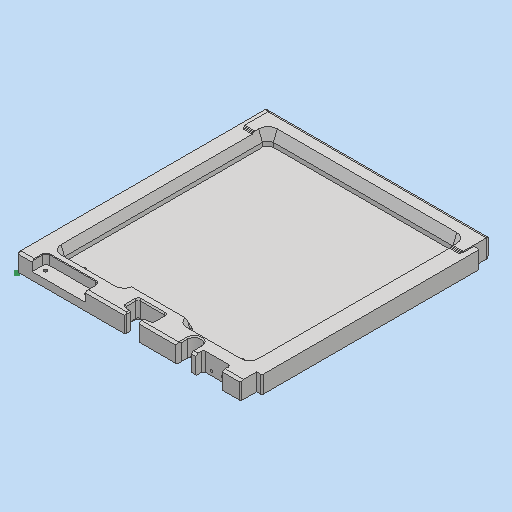
# Autodesk Inventor part: MN0555AN106_G01_100
Saved by Autodesk Inventor 2023.3 (Build 273359000, 359)
## iProperties
RuleStatus: InUse
Created: 2022-12-23
Part Number: MN0555AN106_G01_100
Material: 1.2210 115CrV3
Description: =<RBPARTNOTITLE2>
Document SubType Name: Modeling
Designer: ric7an
Mass: 3076.42 g
Surface Area: 1198.55 cm^2
Volume: 394.412 cm^3
Density: 7.8 g/cm^3
Appearance: silber AnP
AnP_Kategorie: 1
AnP_Material: =<Material>
MaxAbmaße: 18 x 275 x 212 (FM)
AnP_TemplVers: 20200821
RBDOCUMENTTYPE: DRF
RBDOCUMENTVERSION: 00
RBDRAWINGMAINSCALE: 1:1
RBDRAWINGMISSINGSPEC: --
RBDRAWINGVOLUME: --
RBDSV1: 0850
RBGBEDGESIN1: +0,5
RBGBEDGESIN2: +0,2
RBGBEDGESOUT1: -0,3
RBGBEDGESOUT2: -0,1
RBMATERIAL: =<Material>
RBMATMEETS: --
RBMATNO: =<Part Number>
RBPARTMADEOF: 18 x 275 x 212 (FM)
RBPARTNO: SIEHE MNR
RBPARTNOTITLE1: manufactured part
RBPARTNOTITLE2: Anfertigungsteil
RBPARTSAFETYINDICATOR: --
RBSURFACE: chemically nickel-coated
RBSURFACE2: chem. vernickelt
RBZEDGESNORM: ISO13715:2002-06
RBZGENDIMCLASS: m
RBZGENDIMNORM: ISO 2768-1:1989-11
RBZGENGEOCLASS: H
RBZGENGEONORM: ISO 2768-2:1989-11
RBZSURFACENORM: ISO13D2:2002-02
RBZTOLERANCENORM: ISO 14405-1:2010-12
Author: ric7an
Keywords: =<RBPARTMADEOF>
Comments: =<RBSURFACE2>
Revision Number: 01
Autodesk Inventor part; units mm, degrees
ref_plane "YZ Plane" through (0, 0, 0) normal (1, 0, 0) x (0, 1, 0)
ref_plane "XZ Plane" through (0, 0, 0) normal (0, 1, 0) x (-1, 0, 0)
ref_plane "XY Plane" through (0, 0, 0) normal (0, 0, 1) x (1, 0, 0)
sketch "Skizze1" plane through (0, 0, 0) normal (0, 0, 1) x (1, 0, 0)
  line L0 (-106, 230) -> (106, 230)
  line L1 (106, 230) -> (106, 0)
  line L2 (106, 0) -> (-106, 0)
  line L3 (-106, 0) -> (-106, 230)
  line L4 (0, 276) -> (0, -46) projected
  line L5 (-148.4, 0) -> (148.4, 0) projected
  point P0 (0, 0)
  dimension "d0" = 212
  dimension "d1" = 230
  constraints: 8 end point, 2 parallel, 1 collinear, 1 horizontal, 1 perpendicular, 1 other
  measures "d0" distance of L0.start L0.end
  measures "d1" distance of L0.end L1.end
extrude "Extrusion1" add sketch "Skizze1" along normal blind 18
sketch "Skizze3" plane through (0, 0, 18) normal (0, 0, 1) x (1, 0, 0)
  line L0 (-106, 0) -> (106, 0) projected
  line L1 (-106, 0) -> (106, 0) projected
  line L2 (84, 0) -> (59, 0)
  line L3 (59, 0) -> (59, 7.5)
  line L4 (59, 7.5) -> (84, 7.5)
  line L5 (84, 7.5) -> (84, 0)
  line L6 (-43, 0) -> (-92, 0)
  line L7 (-92, 0) -> (-92, 13)
  line L8 (-92, 13) -> (-43, 13)
  line L9 (-43, 13) -> (-43, 0)
  line L10 (0, 277.2) -> (0, -53.2) projected
  line L11 (48, 0) -> (48, 10) construction
  line L12 (54, 0) -> (54, 10)
  line L13 (42, 10) -> (42, 0)
  arc A0 (42, 0) -> (54, 0) centre (48, 0) ccw
  arc A1 (54, 10) -> (42, 10) centre (48, 10) ccw
  line L14 (71.5, 7.5) -> (71.5, 0) construction
  point P0 (48, 5)
  point P1 (42, 0)
  point P2 (54, 0)
  dimension "d19" = 25
  dimension "d20" = 49
  dimension "d21" = 13
  dimension "d22" = 7.5
  dimension "d93" = 43
  dimension "d117" = 10
  dimension "d118" = 48
  dimension "d119" = 12
  dimension "d141" = 71.5
  constraints: 26 end point, 5 parallel, 4 point on circle, 4 tangent, 3 midpoint, 3 perpendicular, 2 centre point, 2 horizontal, 2 point on line, 1 collinear
  measures "d19" distance of L3.end L4.end
  measures "d20" distance of L7.end L8.end
  measures "d21" distance of L6.end L7.end
  measures "d22" distance of L4.end L2.start
  measures "d93" distance between parallel lines of L10 L9
  measures "d117" distance of L13.start L13.end
  measures "d118" distance from line of point (48, 5) L10
  measures "d119" distance between parallel lines of L13 L12
  measures "d141" distance between parallel lines of L14 L10
sketch "Skizze5" plane through (0, 0, 18) normal (0, 0, 1) x (1, 0, 0)
  line L0 (-88, 214) -> (88, 214)
  line L1 (88, 214) -> (88, 21)
  line L2 (28, 28) -> (-28, 28)
  line L3 (-88, 21) -> (-88, 214)
  line L4 (-28, 28) -> (-28, 21)
  line L5 (-28, 21) -> (-88, 21)
  line L6 (28, 28) -> (28, 21)
  line L7 (28, 21) -> (88, 21)
  line L8 (-106, 0) -> (106, 0) projected
  point P0 (0, 0)
  point P1 (0, 214)
  dimension "d159" = 176
  dimension "d160" = 28
  dimension "d208" = 7
  dimension "d209" = 60
  dimension "d248" = 214
  constraints: 16 end point, 2 collinear, 2 horizontal, 2 parallel, 2 perpendicular, 2 vertical, 1 midpoint, 1 vertical alignment
  measures "d159" distance of L1.end L3.start
  measures "d160" distance from line of point (0, 0) L2
  measures "d208" distance between parallel lines of L2 L7
  measures "d209" distance of L6.end L1.end
  measures "d248" distance between parallel lines of L8 L0
extrude "Extrusion5" cut sketch "Skizze5" against normal blind 13
sketch "Skizze16" plane through (-106, 0, 0) normal (-1, 0, 0) x (0, 0, 1)
  line L0 (17, 0) -> (17, 203.2679)
  line L1 (17, 203.2679) -> (18, 205)
  line L2 (18, 205) -> (18, 230)
  line L3 (18, 230) -> (18, 230)
  line L4 (18, 230) -> (18, 0)
  line L5 (18, 0) -> (17, 0)
  line L6 (0, 230) -> (0, 0) projected
  line L7 (17, 2.5) -> (15.5566, 0)
  line L8 (15.5566, 0) -> (17, 0)
  line L9 (18, 227) -> (16.2679, 230)
  line L10 (16.2679, 230) -> (18, 230)
  dimension "d122" = 18
  dimension "d125" = 1
  dimension "d126" = 30
  dimension "d127" = 25
  dimension "d189" = 30
  dimension "d190" = 2.5
  dimension "d192" = 3
  dimension "d193" = 30
  constraints: 20 end point, 3 perpendicular, 2 horizontal, 2 point on line, 1 coincident, 1 vertical
  measures "d122" distance between parallel lines of L6 L2
  measures "d125" distance between parallel lines of L0 L2
  measures "d126" angle of L2 L1
  measures "d127" distance of L1.end L2.end
  measures "d189" angle of L0 L7
  measures "d190" vertical distance of L7.start L7.end
  measures "d192" vertical distance of L9.start L9.end
  measures "d193" angle of L2 L9
extrude "Extrusion12" cut sketch "Skizze16" against normal through all
fillet "Rundung10" radius 5 6 edges at (88, 214, 11.5) (-88, 214, 11.5) (88, 21, 11) (-88, 21, 11) (-28, 21, 11) (28, 21, 11)
chamfer "Fase25" distance 8 angle 22 3 edges at (88, 114.634, 17) (86.5355, 22.4645, 17) (58, 21, 17) measured on face at (58, 21, 16.5) measured on face at (88, 114.634, 16.5) measured on face at (86.5355, 22.4645, 16.5)
chamfer "Fase26" distance 8 angle 22 3 edges at (-88, 114.634, 17) (-86.5355, 22.4645, 17) (-58, 21, 17) measured on face at (-86.5355, 22.4645, 16.5) measured on face at (-88, 114.634, 16.5) measured on face at (-58, 21, 16.5)
chamfer "Fase27" distance 9 angle 22 5 edges at (0, 214, 18) (86.5355, 212.5355, 18) (88, 207, 18) (-86.5355, 212.5355, 18) (-88, 207, 18) measured on face at (0, 214, 17.5) measured on face at (-88, 207, 17.5) measured on face at (88, 207, 17.5) measured on face at (-86.5355, 212.5355, 17.5) measured on face at (86.5355, 212.5355, 17.5)
sketch "Skizze15" plane through (-106, 0, 0) normal (-1, 0, 0) x (0, 0, 1)
  point P0 (0, 0)
extrude "Extrusion3" cut sketch "Skizze3" against normal through all contours L13 A1 L12 L0 | L3 L4 L5 L0
chamfer "Fase28" distance 4 angle 20 1 edges at (54, 0, 7.7783) measured on face at (54, 0.5, 7.7783)
chamfer "Fase29" distance 4 angle 20 1 edges at (42, 0, 7.7783) measured on face at (42, 0.5, 7.7783)
extrude "Extrusion11" cut sketch "Skizze3" against normal blind 10 contours L7 L8 L9 L0
sketch "Skizze11" plane through (0, 0, 18) normal (0, 0, 1) x (1, 0, 0)
  line L0 (106, 0) -> (106, 230) projected
  line L1 (82, 0) -> (106, 0) projected
  line L2 (106, 0) -> (101, 0)
  line L3 (101, 0) -> (101, 14.5)
  line L4 (101, 14.5) -> (106, 14.5)
  line L5 (106, 14.5) -> (106, 0)
  line L6 (106, 230) -> (101, 230)
  line L7 (101, 230) -> (101, 215.5)
  line L8 (101, 215.5) -> (106, 215.5)
  line L9 (106, 215.5) -> (106, 230)
  point P0 (0, 0)
  point P1 (101, 0)
  point P2 (106, 215.5)
  dimension "d88" = 5
  dimension "d89" = 14.5
  dimension "d92" = 14.5
  constraints: 16 end point, 5 parallel, 2 horizontal, 2 perpendicular
  measures "d88" distance of L3.end L4.end
  measures "d89" distance of L2.end L3.end
  measures "d92" distance of L6.end L7.end
extrude "Extrusion8" cut sketch "Skizze11" against normal through all
fillet "Rundung9" radius 2 4 edges at (98.6161, 203.2679, 17) (-98.6161, 203.2679, 17) (98.8181, 205, 18) (-98.8181, 205, 18)
sketch "Skizze12" plane through (0, 0, 17) normal (0, 0, 1) x (1, 0, 0)
  line L0 (-13, 19) -> (13, 19)
  line L1 (13, 19) -> (13, 6)
  line L2 (13, 6) -> (-13, 6)
  line L3 (-13, 6) -> (-13, 19)
  line L4 (-6, 6) -> (6, 6)
  line L5 (6, 6) -> (6, 0)
  line L6 (6, 0) -> (-6, 0)
  line L7 (-6, 0) -> (-6, 6)
  line L8 (0, 276) -> (0, -46) projected
  line L9 (40.5441, 0) -> (-43, 0) projected
  point P0 (0, 0)
  point P1 (0, 6)
  point P2 (0, 19)
  point P3 (6, 6)
  dimension "d94" = 6
  dimension "d96" = 12
  dimension "d97" = 26
  dimension "d247" = 19
  constraints: 16 end point, 4 parallel, 2 horizontal, 2 perpendicular, 1 collinear, 1 point on line, 2 other
  measures "d94" distance of L4.end L5.end
  measures "d96" distance between parallel lines of L7 L5
  measures "d97" distance of L0.start L0.end
  measures "d247" distance between parallel lines of L9 L0
extrude "Extrusion9" cut sketch "Skizze12" against normal through all
fillet "Rundung4" radius 2 4 edges at (-13, 6, 8.5) (-13, 19, 8.5) (13, 19, 8.5) (13, 6, 8.5)
chamfer "Fase17" distance 1.5 angle 30 9 edges at (0, 19, 17) (12.4142, 18.4142, 17) (13, 12.5, 17) (12.4142, 6.5858, 17) (8.5, 6, 17) (-12.4142, 18.4142, 17) (-13, 12.5, 17) (-12.4142, 6.5858, 17) (-8.5, 6, 17) measured on face at (13, 12.5, 16.5) measured on face at (12.4142, 18.4142, 16.5) measured on face at (8.5, 6, 16.5) measured on face at (0, 19, 16.5) measured on face at (-8.5, 6, 16.5) measured on face at (-13, 12.5, 16.5) measured on face at (-12.4142, 6.5858, 16.5) measured on face at (-12.4142, 18.4142, 16.5) measured on face at (12.4142, 6.5858, 16.5)
chamfer "Fase18" distance 1.5 angle 30 9 edges at (0, 19, 0) (-12.4142, 18.4142, 0) (-13, 12.5, 0) (-12.4142, 6.5858, 0) (-8.5, 6, 0) (12.4142, 18.4142, 0) (13, 12.5, 0) (12.4142, 6.5858, 0) (8.5, 6, 0) measured on face at (13, 12.5, 0.5) measured on face at (0, 19, 0.5) measured on face at (8.5, 6, 0.5) measured on face at (-8.5, 6, 0.5) measured on face at (12.4142, 6.5858, 0.5) measured on face at (-12.4142, 6.5858, 0.5) measured on face at (-13, 12.5, 0.5) measured on face at (-12.4142, 18.4142, 0.5) measured on face at (12.4142, 18.4142, 0.5)
sketch "Skizze17" plane through (-106, 250, 18) normal (0, 0, 1) x (1, 0, 0)
  line L0 (5, -20) -> (0, -20)
  line L1 (0, -20) -> (0, -47.2679)
  line L2 (0, -47.2679) -> (5, -47.2679)
  line L3 (5, -47.2679) -> (5, -20)
  line L4 (207, -20) -> (212, -20)
  line L5 (212, -20) -> (212, -47.2679)
  line L6 (212, -47.2679) -> (207, -47.2679)
  line L7 (207, -47.2679) -> (207, -20)
  line L8 (212, -44.4641) -> (212, -34.5) projected
  line L9 (0, -47.2679) -> (14.7678, -47.2679) projected
  line L10 (197.2322, -47.2679) -> (212, -47.2679) projected
  line L11 (207, -34.5) -> (207, -23) projected
  line L12 (0, -23) -> (0, -20) projected
  line L13 (0, -20) -> (207, -20) projected
  line L14 (5, -44.2679) -> (6.0919, -47.2679)
  line L15 (207, -44.2679) -> (205.9081, -47.2679)
  point P0 (212, 0)
  point P1 (5, -47.2679)
  dimension "d226" = 20
  dimension "d227" = 3
  dimension "d228" = 20
  constraints: 20 end point, 7 collinear, 5 point on line, 4 parallel, 2 horizontal, 2 perpendicular, 1 horizontal alignment
  measures "d226" angle of L7 L15
  measures "d227" distance from line of L10 L15.start
  measures "d228" angle of L14 L3
extrude "Extrusion13" cut sketch "Skizze17" against normal up to surface (1 mm away)
sketch "Skizze18" plane through (0, 0, 8) normal (0, 0, 1) x (1, 0, 0)
  line L0 (-43, 0) -> (-92, 0) projected
  line L1 (-67.5, 13) -> (-67.5, -16.7627) construction
  line L2 (-92, 13) -> (-43, 13) projected
  point P0 (0, 0)
  point P1 (-86.5, 7)
  point P2 (-48.5, 7)
  dimension "d137" = 38
  dimension "d138" = 7
  constraints: 2 end point, 1 midpoint, 1 symmetric about line, 1 vertical
  measures "d137" distance of point (-48.5, 7) point (-86.5, 7)
  measures "d138" distance from line of L0 point (-48.5, 7)
hole "Bohrung1" at (-86.5, 7, 8) at (-48.5, 7, 8) direction (0, 0, -1) diameter 3.242 end through all thread size "M4x0.7" designation "M4" class "6H" standard "ISO Metric profile"
fillet "Rundung6" radius 3 2 edges at (-92, 13, 12.5) (-43, 13, 12.5)
chamfer "Fase10" distance 8 angle 22 1 edges at (0, 28, 17) measured on face at (0, 28, 16.5)
sketch "Skizze19" plane through (59, 7.5, 18) normal (0, -1, 0) x (1, 0, 0)
  line L0 (25, -18) -> (0, -18) projected
  line L1 (12.5, -18) -> (12.5, -13)
  point P0 (-59, -18)
  point P1 (7.5, -14)
  point P2 (17.5, -14)
  dimension "d149" = 4
  dimension "d150" = 10
  dimension "d224" = 5
  constraints: 2 end point, 1 midpoint, 1 symmetric about line, 1 vertical
  measures "d149" distance from line of L0 point (7.5, -14)
  measures "d150" distance of point (7.5, -14) point (17.5, -14)
  measures "d224" distance of L1.start L1.end
hole "Bohrung2" at (66.5, 7.5, 4) at (76.5, 7.5, 4) direction (0, 1, 0) diameter 2.459 depth 8.8 tip angle 118 thread size "M3x0.5" designation "M3" class "6H" standard "ISO Metric profile"
sketch "Skizze22" plane through (0, 0, 0) normal (0, 0, -1) x (-1, 0, 0)
  line L0 (-101, 230) -> (106, 230) projected
  line L1 (0, 230) -> (0, 0)
  point P0 (73, 220)
  point P1 (-73, 220)
  point P2 (73, 29)
  point P3 (-73, 29)
  point P4 (1, 276)
  dimension "d182" = 146
  dimension "d183" = 10
  dimension "d202" = 191
  constraints: 2 end point, 2 symmetric about line, 1 coincident, 1 point on line, 1 vertical, 1 vertical alignment
  measures "d182" distance of point (73, 220) point (-73, 220)
  measures "d183" distance from line of point (-73, 220) L0
  measures "d202" distance of point (-73, 29) point (-73, 220)
hole "Bohrung3" at (-73, 220, 0) at (73, 220, 0) at (73, 29, 0) at (-73, 29, 0) direction (0, 0, 1) diameter 4.134 depth 14.2 tip angle 118 thread size "M5x0.8" designation "M5" class "6H" standard "ISO Metric profile"
chamfer "Fase23" distance 1 angle 45 7 edges at (-106, 229.366, 16.634) (106, 215.5, 8.5) (106, 14.5, 8.5) (101, 0, 7.7783) (-106, 0, 7.7783) (-106, 1.25, 16.2783) (-106, 115.616, 17)
chamfer "Fase24" distance 1 angle 45 25 edges at (-6, 2.567, 0) (-55.5, 0, 0) (92, 0, 0) (23.2721, 0, 0) (57.2279, 0, 0) (6, 2.567, 0) (42, 7, 0) (48, 16, 0) (54, 7, 0) (-106, 115.5, 0) (-2.5, 230, 0) (101, 222.75, 0) (103, 215.5, 0) (106, 115, 0) (103, 14.5, 0) (101, 7.75, 0) (-6, 6, 8.5) (-6, 0, 7.7783) (6, 6, 8.5) (6, 0, 7.7783) (48, 16, 17) (54, 7, 17) (42, 7, 17) (-6, 3.817, 17) (6, 3.817, 17)
fillet "Rundung11" radius 2 2 edges at (59, 7.5, 8.5) (84, 7.5, 8.5)
chamfer "Fase30" distance 0.5 angle 45 5 edges at (-67.5, 13, 17) (-43.8787, 12.1213, 17) (-43, 6.25, 17) (-91.1213, 12.1213, 17) (-92, 6.25, 17)
sketch "Skizze23" plane through (-105, 230, 16.2679) normal (0, 1, 0) x (1, 0, 0)
  line L0 (64.75, 13.75) -> (145.25, 13.75)
  line L1 (145.25, 13.75) -> (145.25, 1.25)
  line L2 (145.25, 1.25) -> (64.75, 1.25)
  line L3 (64.75, 1.25) -> (64.75, 13.75)
  line L4 (105, 19.8679) -> (105, -5.3321) projected
  line L5 (0, 0) -> (206, 0) projected
  point P0 (105, 16.2679)
  point P1 (205, 0)
  dimension "d232" = 12.5
  dimension "d233" = 80.5
  dimension "d234" = 1.25
  constraints: 8 end point, 2 parallel, 1 horizontal, 1 perpendicular, 1 other
  measures "d232" distance of L0.end L1.end
  measures "d233" distance of L0.start L0.end
  measures "d234" distance between parallel lines of L5 L2
extrude "Extrusion15" cut sketch "Skizze23" against normal blind 1.5
fillet "Rundung12" radius 2.25 4 edges at (40.25, 229.25, 2.5179) (40.25, 229.25, 15.0179) (-40.25, 229.25, 15.0179) (-40.25, 229.25, 2.5179)
sketch "Skizze24" plane through (-105, 228.5, 16.2679) normal (0, 1, 0) x (1, 0, 0)
  line L0 (105, 19.8679) -> (105, -5.3321) projected
  line L1 (143, 1.25) -> (67, 1.25) projected
  point P0 (105, 16.2679)
  point P1 (68.5, 7.5)
  point P2 (141.5, 7.5)
  dimension "d238" = 73
  dimension "d239" = 6.25
  constraints: 1 symmetric about line
  measures "d238" distance of point (141.5, 7.5) point (68.5, 7.5)
  measures "d239" distance from line of L1 point (68.5, 7.5)
hole "Bohrung4" at (36.5, 228.5, 8.7679) at (-36.5, 228.5, 8.7679) direction (0, -1, 0) diameter 2.459 depth 8.8 tip angle 118 thread size "M3x0.5" designation "M3" class "6H" standard "ISO Metric profile"
chamfer "Fase31" distance 1.5 angle 60 1 edges at (-106, 230, 8.0566) measured on face at (-105.5, 230, 8.0566)
chamfer "Fase32" distance 1.5 angle 60 1 edges at (101, 230, 8.634) measured on face at (100.5, 230, 8.634)
equation "\"d92\" = d89"
